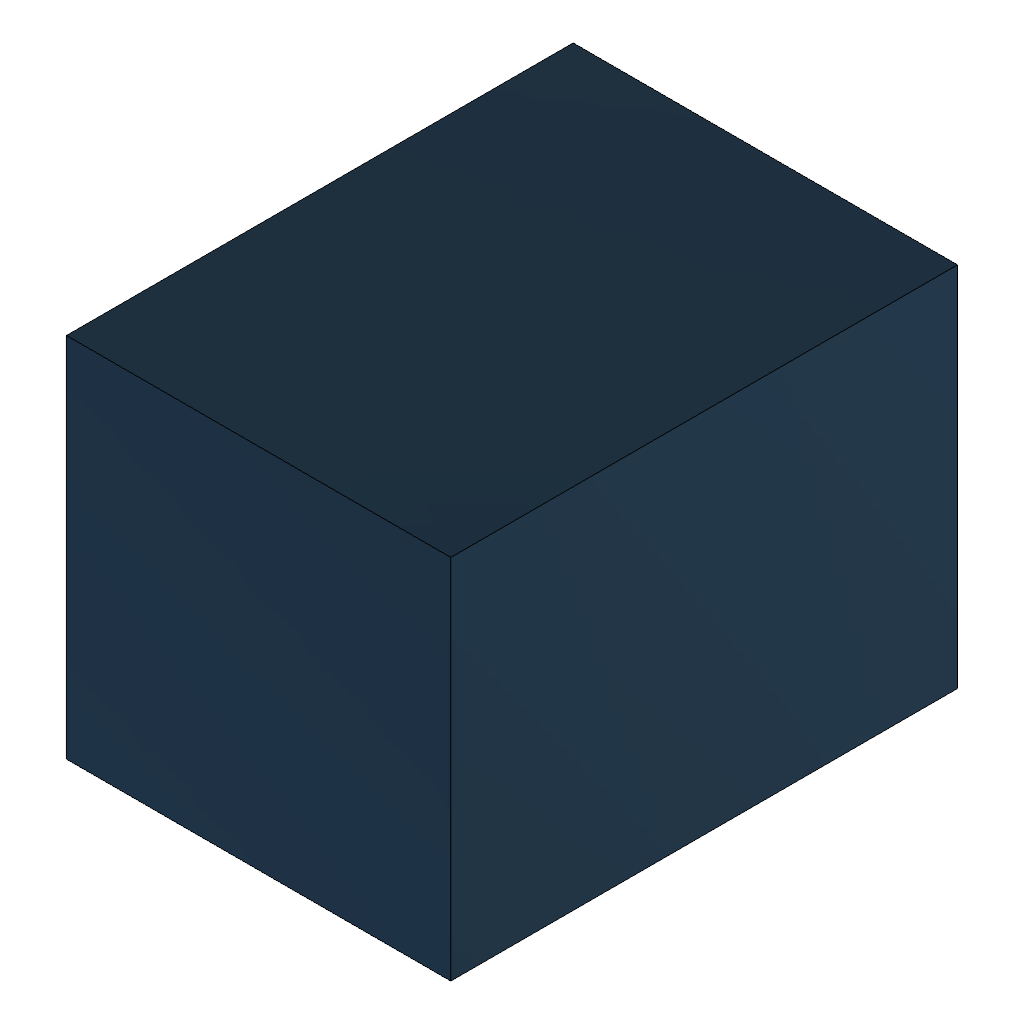
StripCuboidReemitted (Autodesk Fusion 360 design; units mm, degrees)
Autodesk Fusion 360 part; units mm, degrees
sketch "Public Profile" plane through (0, 0, 0) normal (0, 0, 1) x (1, 0, 0)
  line L0 (0, 0) -> (22, 0)
  line L1 (22, 0) -> (22, 29)
  line L2 (22, 29) -> (0, 29)
  line L3 (0, 29) -> (0, 0)
  dimension "d6" = 22
  dimension "d7" = 29
  constraint horizontal L0
  constraint vertical L1
  constraint horizontal L2
  constraint vertical L3
  measures "d6" horizontal distance of L0.start L0.end
  measures "d7" vertical distance of L0.start L2.end
extrude "Public Extrusion" add sketch "Public Profile" along normal blind 21
equation "publicHeight = 21 mm"
equation "d2 = publicHeight"
equation "rectangleWidth = 22 mm"
equation "rectangleDepth = 29 mm"
equation "d6 = rectangleWidth"
equation "d7 = rectangleDepth"
